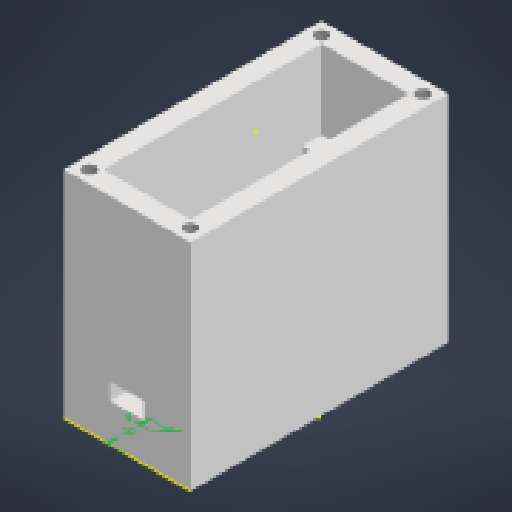
# Autodesk Inventor part: Hộp khớp 2
Saved by Autodesk Inventor 2026.2 (Build 302298000, 298)
## iProperties
Created: 2026-01-28
Part Number: Hộp khớp 2
Material: Generic
Document SubType Name: Modeling
Designer: thita
Density: 1 g/cm^3
Appearance: Default
Author: thita
Autodesk Inventor part; units mm, degrees
ref_plane "YZ Plane" through (0, 0, 0) normal (1, 0, 0) x (0, 1, 0)
sketch "Sketch1" plane through (0, 0, 0) normal (0, 1, 0) x (-1, 0, 0)
  line L0 (15, -30.5) -> (-15, -30.5)
  line L1 (-15, -30.5) -> (-15, 30.5)
  line L2 (-15, 30.5) -> (15, 30.5)
  line L3 (15, 30.5) -> (15, -30.5)
  line L4 (15, -30.5) -> (-15, 30.5) construction
  line L5 (-15, -30.5) -> (15, 30.5) construction
  point P0 (0, 0)
  dimension "d0" = 30
  dimension "d1" = 61
  constraints: 12 end point, 2 midpoint, 2 parallel, 1 horizontal, 1 perpendicular
  measures "d0" distance of L0.start L0.end
  measures "d1" distance of L0.end L1.end
extrude "Extrusion1" add sketch "Sketch1" along normal blind 51
sketch "Sketch2" plane through (0, 51, 0) normal (0, 1, 0) x (1, 0, 0)
  line L0 (10.3, -25.8) -> (-10.3, -25.8)
  line L1 (-10.3, -25.8) -> (-10.3, 25.8)
  line L2 (-10.3, 25.8) -> (10.3, 25.8)
  line L3 (10.3, 25.8) -> (10.3, -25.8)
  line L4 (10.3, -25.8) -> (-10.3, 25.8) construction
  line L5 (-10.3, -25.8) -> (10.3, 25.8) construction
  line L6 (0, -24.3) -> (0, 24.3)
  line L7 (-4.95, -24.3) -> (4.95, -24.3)
  line L8 (-4.95, 24.3) -> (4.95, 24.3)
  point P0 (0, 0)
  dimension "d8" = 20.6
  dimension "d9" = 51.6
  dimension "d10" = 48.6
  dimension "d11" = 9.9
  dimension "d12" = 9.9
  constraints: 18 end point, 5 midpoint, 3 parallel, 2 horizontal, 1 perpendicular, 1 vertical
  measures "d8" distance of L0.start L0.end
  measures "d9" distance of L0.end L1.end
  measures "d10" distance of L6.start L6.end
  measures "d11" distance of L7.start L7.end
  measures "d12" distance of L8.start L8.end
sketch "Sketch3" plane through (0, 0, 0) normal (0, -1, 0) x (1, 0, 0)
  line L0 (-15, 30.5) -> (15, 30.5) projected
  line L1 (0, 30.5) -> (0, 20.5)
  circle A0 centre (0, 20.5) radius 2
  point P0 (0, 0)
  dimension "d6" = 10
  dimension "d7" = 4
  constraints: 2 end point, 1 centre point, 1 coincident, 1 midpoint, 1 vertical
  measures "d6" distance of L1.start L1.end
  measures "d7" diameter of A0
extrude "Extrusion2" cut sketch "Sketch2" against normal blind 46
sketch "Sketch4" plane through (0, 5, 0) normal (0, 1, 0) x (1, 0, 0)
  line L0 (0, 25.8) -> (0, 25.3361)
  line L1 (-10, -25.8) -> (10, -25.8)
  line L2 (10.3, -25.8) -> (-10.3, -25.8) projected
  line L3 (-10, 25.8) -> (10, 25.8)
  line L4 (-10, -25.8) -> (-10.3, -25.8)
  line L5 (-10.3, -25.8) -> (-10.3, 25.8) projected
  line L6 (-10.3, -25.8) -> (-10.3, -20.3)
  line L7 (-10.3, -20.3) -> (-10, -20.3)
  line L8 (10, -20.3) -> (10.3, -20.3)
  line L9 (10.3, -20.3) -> (10.3, -25.8)
  line L10 (10, -25.8) -> (10.3, -25.8)
  line L11 (-10, 20.3) -> (-10.3, 20.3)
  line L12 (-10.3, 20.3) -> (-10.3, 25.8)
  line L13 (-10, 25.8) -> (-10.3, 25.8)
  line L14 (-10.3, 25.8) -> (10.3, 25.8) projected
  line L15 (10, 25.8) -> (10.3, 25.8)
  line L16 (10.3, 25.8) -> (10.3, 20.3)
  line L17 (10.3, 20.3) -> (10, 20.3)
  line L18 (10.3, -20.3) -> (10.3, -21.3)
  line L19 (10.3, 25.8) -> (10.3, -25.8) projected
  line L20 (10.3, -21.3) -> (-10.3, -21.3)
  line L21 (10.3, 20.3) -> (10.3, 21.3)
  line L22 (10.3, 21.3) -> (-10.3, 21.3)
  point P0 (0, 20.3)
  dimension "d29" = 1
  dimension "d30" = 1
  constraints: 38 end point, 10 perpendicular, 8 point on line, 2 horizontal, 1 collinear, 1 parallel
  measures "d29" distance of L8.end L18.end
  measures "d30" distance of L16.end L21.end
extrude "Extrusion3" add sketch "Sketch4" along normal blind 27.3 contours L2 L5 L20 L9 L1 | L5 L13 L3 L14 L16 L22
sketch "Sketch5" plane through (0, 32.3, 0) normal (0, 1, 0) x (1, 0, 0)
  line L0 (0, 24.3) -> (0, -24.3)
  line L1 (-4.95, -24.3) -> (4.95, -24.3)
  arc A0 (-3.6271, -25.8) -> (-6.2729, -25.8) centre (-4.95, -24.3) ccw
  arc A1 (6.2729, -25.8) -> (3.6271, -25.8) centre (4.95, -24.3) ccw
  line L2 (10.3, -25.8) -> (-10.3, -25.8) projected
  line L3 (-10.3, -25.8) -> (10.3, -25.8)
  point P0 (0, 0)
  point P1 (-6.2729, -25.8)
  point P2 (-3.6271, -25.8)
  dimension "d20" = 48.6
  dimension "d21" = 9.9
  dimension "d22" = 4
  dimension "d23" = 4
  constraints: 6 end point, 4 point on circle, 4 point on line, 2 centre point, 2 coincident, 2 midpoint, 1 collinear, 1 horizontal, 1 vertical
  measures "d20" distance of L0.start L0.end
  measures "d21" distance of L1.start L1.end
  measures "d22" diameter of A0
  measures "d23" diameter of A1
extrude "Extrusion4" cut sketch "Sketch5" against normal blind 6 contours A0 L2 | A1 L2
mirror "Mirror1" about plane through (0, 0, 0) normal (0, 0, 1) of "Extrusion4"
sketch "Sketch6" plane through (10.3, 5, 21.3) normal (0, 0, -1) x (-1, 0, 0)
  line L0 (20.6, 27.3) -> (20.6, 0) projected
  line L1 (0, 0) -> (20.6, 0)
  line L2 (20.6, 0) -> (20.6, 20)
  line L3 (20.6, 20) -> (0, 20)
  line L4 (0, 20) -> (0, 0)
  line L5 (20.6, 0) -> (0, 0)
  point P0 (10.3, -5)
  dimension "d26" = 20
  constraints: 10 end point, 2 perpendicular, 1 collinear, 1 horizontal, 1 point on line
  measures "d26" distance of L0.end L2.end
extrude "Extrusion5" cut sketch "Sketch6" against normal up to surface (4.5 mm away)
mirror "Mirror2" about plane through (0, 0, 0) normal (0, 0, 1) of "Extrusion5"
ref_plane "Work Plane1" through (-15.3617, 45.5, -22.6809) normal (0, 1, 0) x (0, 0, 1)
ref_plane "Work Plane2" through (-5.0723, 46.7, 5.1277) normal (0, 1, 0) x (0, 0, 1)
sketch "Sketch9" plane through (0, 51, 0) normal (0, 1, 0) x (1, 0, 0)
  line L0 (-15, -30.5) -> (15, -30.5) projected
  line L1 (-15, -30.5) -> (-15, -27.5)
  line L2 (-15, -27.5) -> (-12, -27.5)
  circle A0 centre (-12, -27.5) radius 1.5
  line L3 (-15, 0) -> (-12.5, 0)
  line L4 (15, 30.5) -> (-15, 30.5) projected
  line L5 (0, 30.5) -> (0, 27.4428)
  circle A1 centre (-12, 27.5) radius 1.5
  circle A2 centre (12, -27.5) radius 1.5
  circle A3 centre (12, 27.5) radius 1.5
  point P0 (0, 0)
  dimension "d54" = 3
  dimension "d55" = 3
  dimension "d56" = 3
  constraints: 8 end point, 4 centre point, 3 symmetric about line, 2 vertical, 1 coincident, 1 horizontal, 1 midpoint, 1 perpendicular, 3 other
  measures "d54" distance of L0.start L1.end
  measures "d55" distance of L1.end L2.end
  measures "d56" diameter of A0
extrude "Extrusion8" cut sketch "Sketch9" against normal blind 10
thread "Thread9" size "M3x0.5" class "6H" standard "ISO Metric profile" length 12
thread "Thread10" size "M3x0.5" class "6H" standard "ISO Metric profile" length 12
thread "Thread11" size "M3x0.5" class "6H" standard "ISO Metric profile" length 12
thread "Thread12" size "M3x0.5" class "6H" standard "ISO Metric profile" length 12
sketch "Sketch10" plane through (0, 51, 0) normal (0, 1, 0) x (1, 0, 0)
  point P0 (0, 0)
sketch "Sketch11" plane through (15, 0, 30.5) normal (1, 0, 0) x (0, 0, -1)
  point P0 (30.5, 0)
sketch "Sketch12" plane through (-15, 0, 30.5) normal (0, 0, 1) x (1, 0, 0)
  line L0 (15, 0) -> (15, 11)
  line L1 (11, 9) -> (19, 9)
  line L2 (19, 9) -> (19, 13)
  line L3 (19, 13) -> (11, 13)
  line L4 (11, 13) -> (11, 9)
  line L5 (11, 9) -> (19, 13) construction
  line L6 (19, 9) -> (11, 13) construction
  dimension "d67" = 11
  dimension "d72" = 8
  dimension "d73" = 4
  constraints: 14 end point, 2 midpoint, 2 parallel, 2 perpendicular, 1 vertical
  measures "d67" distance of L0.start L0.end
  measures "d72" distance of L1.start L1.end
  measures "d73" distance of L2.end L1.end
extrude "Extrusion9" cut sketch "Sketch12" against normal blind 5
sketch "Sketch13" plane through (0, 32.3, 0) normal (0, 1, 0) x (1, 0, 0)
  line L0 (-10.3, -21.3) -> (-10.3, -25.8) projected
  line L1 (-10.3, -21.3) -> (10.3, -21.3)
  line L2 (10.3, -21.3) -> (10.3, -25.8)
  line L3 (10.3, -25.8) -> (-10.3, -25.8)
  line L4 (-10.3, -25.8) -> (-10.3, -21.3)
  point P0 (0, 0)
  constraints: 8 end point, 2 parallel, 1 horizontal, 1 perpendicular
extrude "Extrusion10" cut sketch "Sketch13" against normal blind 15
sketch "Sketch14" plane through (0, 51, 0) normal (0, 1, 0) x (1, 0, 0)
  line L0 (10.3, 27.5) -> (10.3, -27.5)
  line L1 (10.3, -27.5) -> (-10.3, -27.5)
  line L2 (-10.3, -27.5) -> (-10.3, 27.5)
  line L3 (-10.3, 27.5) -> (10.3, 27.5)
  line L4 (10.3, 27.5) -> (-10.3, -27.5) construction
  line L5 (10.3, -27.5) -> (-10.3, 27.5) construction
  point P0 (0, 0)
  dimension "d76" = 55
  constraints: 12 end point, 2 midpoint, 2 parallel, 1 perpendicular, 1 vertical
  measures "d76" distance of L0.start L0.end
extrude "Extrusion11" cut sketch "Sketch14" against normal up to surface (46 mm away)
sketch "Sketch15" plane through (-10.3, 51, -27.5) normal (0, 0, 1) x (1, 0, 0)
  line L0 (6.4, -19) -> (14.2, -19) construction
  line L1 (20.6, -19) -> (0, -19)
  line L2 (0, 0) -> (0, -46) projected
  line L3 (20.6, 0) -> (20.6, -46) projected
  line L4 (0, -19) -> (20.6, -19)
  line L5 (20.6, -19) -> (20.6, -24)
  line L6 (20.6, -24) -> (0, -24)
  line L7 (0, -24) -> (0, -19)
  point P0 (10.3, -51)
  point P1 (0, -24)
  constraints: 10 end point, 2 horizontal, 2 parallel, 2 point on line, 1 perpendicular
extrude "Extrusion12" add sketch "Sketch15" along normal blind 6
sketch "Sketch16" plane through (-10.3, 32, -27.5) normal (0, 1, 0) x (1, 0, 0)
  arc A0 (4.3, -1.21) -> (6.4, -1.21) centre (5.35, -3.2) ccw projected
  arc A1 (14.2, -1.21) -> (16.3, -1.21) centre (15.25, -3.2) ccw projected
  circle A2 centre (5.35, -3.2) radius 2.25
  circle A3 centre (15.25, -3.2) radius 2.25
  point P0 (10.3, -27.5)
  point P1 (16.3, -1.21)
  point P2 (14.2, -1.21)
  point P3 (6.4, -1.21)
  constraints: 2 centre point, 2 coincident, 2 concentric
extrude "Extrusion13" cut sketch "Sketch16" against normal blind 6
thread "Thread13" size "M4.5x0.75" class "6H" standard "ISO Metric profile" length 12
thread "Thread14" size "M4.5x0.75" class "6H" standard "ISO Metric profile" length 12
body "Solid1"
